831001_P01_HARDWARE-LOCATING-SPIGOT_CAD (Autodesk Fusion 360 design; units mm, degrees)
description: HARDWARE - LOCATING SPIGOT - M6 X Ø8 - STAINLESS | Chốt định vị Ø8 | rev P01 | UNITS MM; MATERIAL STAINLESS A2 (1.4301 OR 1.4305); FINISH PASSIVATED, DEBURRED; ISO 2768-m; PIN Ø8 h9; joints register H-05; PROPOSED; origin on the face it sits on (its rivnut's head)
part number: 831001
Autodesk Fusion 360 part; units mm, degrees
sketch "SKETCH - PIN AND STUD" plane through (0, 0, 0) normal (0, 0, 1) x (1, 0, 0)
  circle A0 centre (0, 0) radius 4
  circle A1 centre (0, 0) radius 3
  dimension "d10" = 8
  dimension "d11" = 6
  constraint coincident A0.centre A1.centre
  measures "d10" diameter of A0
  measures "d11" diameter of A1
extrude "EXTRUDE - PIN D8" add sketch "SKETCH - PIN AND STUD" along normal blind 7.24 contours A0 | A1
extrude "EXTRUDE - M6 STUD" add sketch "SKETCH - PIN AND STUD" against normal blind 8 contours A1
chamfer "CHAMFER - PIN LEAD-IN" distance 1 angle 45 1 edges at (-3.7293, -1.4465, 7.24) tangent chain off
sketch "SKETCH - HEX SOCKET" plane through (0, 0, 7.24) normal (0, 0, 1) x (1, 0, 0)
  circle A0 centre (0, 0) radius 3
  line L0 (2.3094, 0) -> (1.1547, 2)
  line L1 (1.1547, 2) -> (-1.1547, 2)
  line L2 (-1.1547, 2) -> (-2.3094, 0)
  line L3 (-2.3094, 0) -> (-1.1547, -2)
  line L4 (-1.1547, -2) -> (1.1547, -2)
  line L5 (1.1547, -2) -> (2.3094, 0)
  circle A1 centre (0, 0) radius 2.3094 construction
  dimension "d17" = 4.6188
  constraint coincident A0.centre A1.centre
  constraint coincident L0.start A1
  constraint coincident L0.end A1
  constraint coincident L1.end A1
  constraint coincident L2.end A1
  constraint coincident L3.end A1
  constraint coincident L4.end A1
  constraint equal L0 L1
  constraint equal L0 L2
  constraint equal L0 L3
  constraint equal L0 L4
  constraint equal L0 L5
  constraint horizontal L1
  measures "d17" diameter of A1
extrude "CUT - HEX SOCKET 4" cut sketch "SKETCH - HEX SOCKET" against normal blind 3.5 contours L0 L1 L2 L3 L4 L5
thread "THREAD - M6x1 STUD 1" "ISO Metric profile 6.0 M6x1 M6x1 6g" major diameter 5.884 minor diameter 4.7435 pitch 1 angle 60 resizes the face on face at (2.9963, -0.1495, -5.3333)
equation "pin_d = 8 mm" comment "PROPOSED: pin diameter, h9 (joints register H-05); Ø8.5 hole or 8.5 slot in the mating part"
equation "pin_proud = 8 mm" comment "PROPOSED: the pin's top stands this far above the joint face (H-05)"
equation "rivnut_head = 0.76 mm" comment "SOURCE: Sherex CAH3-610-4.2 head 0.76 +-0.08 (joints register SHX)"
equation "pin_len = pin_proud - rivnut_head" comment "CALCULATION: the pin sits on its rivnut's head, so 7.24 long"
equation "thread_d = 6 mm" comment "SOURCE: M6 x 1 into the rivnut 838003 (H-03)"
equation "thread_len = 8 mm" comment "ASSUMPTION: inside the rivnut's 10.16 installed length (SHX); as BASE's copies"
equation "tip_ch = 1 mm" comment "ASSUMPTION: lead-in chamfer on the pin's top, as BASE's copies"
equation "hex_af = 4 mm" comment "ASSUMPTION: hex socket across flats, to set it with threadlocker at the factory"
equation "hex_depth = 3.5 mm" comment "ASSUMPTION: hex socket depth"
equation "d10 = pin_d"
equation "d11 = thread_d"
equation "d12 = pin_len"
equation "d14 = -( thread_len )"
equation "d16 = tip_ch"
equation "d17 = hex_af / cos(30 deg)"
equation "d20 = -( hex_depth )"
named bodies: "LOCATING SPIGOT"
